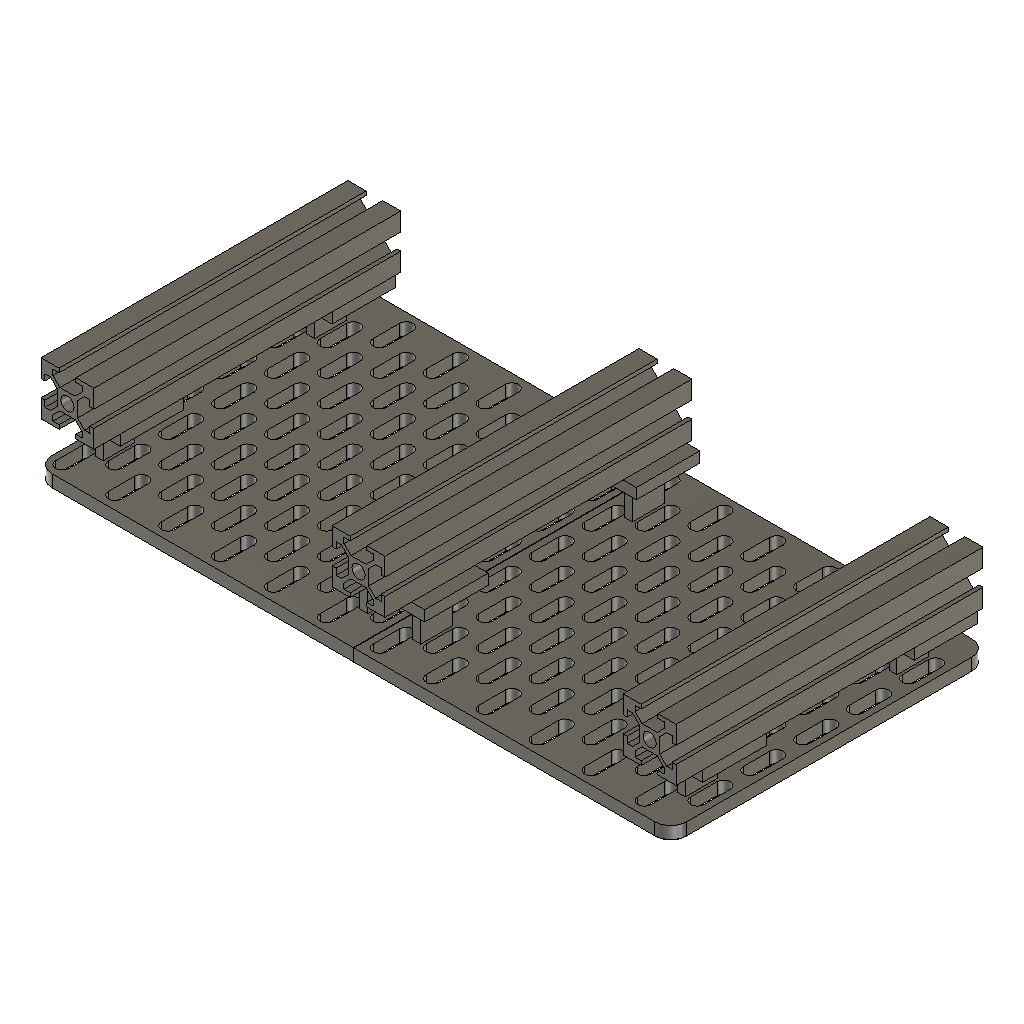
connector-clearance-study (Autodesk Fusion 360 design; units mm, degrees)
part number: 2026-10-29-08-32-22-871
part number: 2026-10-29-08-32-23-128
part number: 2026-10-29-08-32-24-920
part number: 2026-10-29-08-32-26-891
part number: 2026-10-29-08-32-27-039
part number: 2026-10-29-08-32-27-224
part number: 2026-10-29-08-32-27-440
part number: 2026-10-29-08-32-27-695
part number: 2026-10-29-08-32-27-957
part number: 2026-10-29-08-32-28-255
part number: 2026-10-29-08-32-28-585
part number: 2026-10-29-08-32-29-028
part number: 2026-10-29-08-32-29-403
part number: 2026-10-29-08-32-29-813
part number: 2026-10-29-08-32-30-268
part number: 2026-10-29-08-32-30-748
part number: 2026-10-29-08-32-31-271
part number: 2026-10-29-08-32-31-892
part number: 2026-10-29-08-32-32-475
part number: 2026-10-29-08-32-33-065
part number: 2026-10-29-08-32-33-695
part number: 2026-10-29-08-32-34-350
part number: 2026-10-29-08-32-35-130
part number: 2026-10-29-08-32-35-863
part number: 2026-10-29-08-32-36-625
part number: 2026-10-29-08-32-37-418
part number: 2026-10-29-08-32-38-300
part number: 2026-10-29-08-32-39-297
part number: 2026-10-29-08-32-40-270
part number: 2026-10-29-08-32-41-258
part number: 2026-10-29-08-32-42-385
part number: 2026-10-29-08-32-43-503
part number: 2026-10-29-08-32-44-600
part number: 2026-10-29-08-32-45-846
part number: 2026-10-29-08-32-47-039
part number: 2026-10-29-08-32-48-317
part number: 2026-10-29-08-32-49-540
part number: 2026-10-29-08-32-50-716
part number: 2026-10-29-08-32-52-129
part number: 2026-10-29-08-32-53-482
part number: 2026-10-29-08-32-54-896
part number: 2026-10-29-08-32-56-506
part number: 2026-10-29-08-33-14-715
part number: 2026-10-29-08-33-36-199
Autodesk Fusion 360 part; units mm, degrees
(part 1 of 3)
sketch "01 Panel blank sketch" plane through (0, 0, 0) normal (0, 0, 1) x (1, 0, 0) in component "Panel left - restored slot field"
  line L0 (0.1, 0.1) -> (119.9, 0.1)
  line L1 (119.9, 0.1) -> (119.9, 119.9)
  line L2 (119.9, 119.9) -> (0.1, 119.9)
  line L3 (0.1, 119.9) -> (0.1, 0.1)
  dimension "d58" = 0.1
  dimension "d59" = 0.1
  dimension "d60" = 119.8
  dimension "d61" = 119.8
  constraint horizontal L0
  constraint vertical L1
  constraint horizontal L2
  constraint vertical L3
  measures "d58" horizontal distance of origin L0.start
  measures "d59" vertical distance of origin L0.start
  measures "d60" horizontal distance of L0.start L0.end
  measures "d61" vertical distance of L0.end L1.end
extrude "01 Panel blank" add sketch "01 Panel blank sketch" along normal blind 5 makes body 1 in component "Panel left - restored slot field"
fillet "02 Exterior corner rounds" radius 6 2 edges at (0.1, 119.9, 2.5) (0.1, 0.1, 2.5) on bodies 1 in component "Panel left - restored slot field"
sketch "03 Complete A field constrained seed" plane through (0, 0, 0) normal (0, 0, 1) x (1, 0, 0) in component "Panel left - restored slot field"
  line L0 (7.5, 5) -> (7.5, 15)
  arc A0 (7.5, 15) -> (2.5, 15) centre (5, 15) ccw
  line L1 (2.5, 15) -> (2.5, 5)
  arc A1 (2.5, 5) -> (7.5, 5) centre (5, 5) ccw
  line L2 (5, 5) -> (5, 15) construction
  line L3 (5, 5) -> (15, 5) construction
  dimension "d66" = 5
  dimension "d67" = 10
  dimension "d68" = 90
  dimension "d69" = 10
  dimension "d70" = 5
  dimension "d71" = 5
  constraint tangent L0 A0
  constraint tangent A0 L1
  constraint tangent L1 A1
  constraint tangent L0 A1
  constraint parallel L0 L1
  constraint horizontal L3
  measures "d66" diameter of A0
  measures "d67" distance of A1.centre A0.centre
  measures "d68" angle of L2 L3
  measures "d69" horizontal distance of A1.centre L3.end
  measures "d70" horizontal distance of origin A1.centre
  measures "d71" vertical distance of origin A1.centre
extrude "03 Complete A field through cut" cut sketch "03 Complete A field constrained seed" along normal blind 5 bodies 1 in component "Panel left - restored slot field"
pattern_linear "03 Complete A field lattice" count 6 spacing 20 along (1, 0, 0) count 6 spacing 20 along (0, 1, 0) of "03 Complete A field through cut" in component "Panel left - restored slot field"
sketch "04 Complete B field - finished top and bottom constrained seed" plane through (0, 0, 0) normal (0, 0, 1) x (1, 0, 0) in component "Panel left - restored slot field"
  line L0 (17.5, 15) -> (17.5, 25)
  arc A0 (17.5, 25) -> (12.5, 25) centre (15, 25) ccw
  line L1 (12.5, 25) -> (12.5, 15)
  arc A1 (12.5, 15) -> (17.5, 15) centre (15, 15) ccw
  line L2 (15, 15) -> (15, 25) construction
  line L3 (15, 15) -> (25, 15) construction
  dimension "d78" = 5
  dimension "d79" = 10
  dimension "d80" = 90
  dimension "d81" = 10
  dimension "d82" = 15
  dimension "d83" = 15
  constraint tangent L0 A0
  constraint tangent A0 L1
  constraint tangent L1 A1
  constraint tangent L0 A1
  constraint parallel L0 L1
  constraint horizontal L3
  measures "d78" diameter of A0
  measures "d79" distance of A1.centre A0.centre
  measures "d80" angle of L2 L3
  measures "d81" horizontal distance of A1.centre L3.end
  measures "d82" horizontal distance of origin A1.centre
  measures "d83" vertical distance of origin A1.centre
extrude "04 Complete B field - finished top and bottom through cut" cut sketch "04 Complete B field - finished top and bottom constrained seed" along normal blind 5 bodies 1 in component "Panel left - restored slot field"
pattern_linear "04 Complete B field - finished top and bottom lattice" count 6 spacing 20 along (1, 0, 0) count 5 spacing 20 along (0, 1, 0) of "04 Complete B field - finished top and bottom through cut" in component "Panel left - restored slot field"
fillet "05 Rounded entrances and edges" radius 0.4 2 faces at (114.0711, 114.131, 0) (114.0711, 114.131, 0) on bodies 1 in component "Panel left - restored slot field"
sketch "01 Panel blank sketch (2)" plane through (0, 0, 0) normal (0, 0, 1) x (1, 0, 0) in component "Panel right - restored slot field"
  line L0 (120.1, 0.1) -> (239.9, 0.1)
  line L1 (239.9, 0.1) -> (239.9, 119.9)
  line L2 (239.9, 119.9) -> (120.1, 119.9)
  line L3 (120.1, 119.9) -> (120.1, 0.1)
  dimension "d92" = 120.1
  dimension "d93" = 0.1
  dimension "d94" = 119.8
  dimension "d95" = 119.8
  constraint horizontal L0
  constraint vertical L1
  constraint horizontal L2
  constraint vertical L3
  measures "d92" horizontal distance of origin L0.start
  measures "d93" vertical distance of origin L0.start
  measures "d94" horizontal distance of L0.start L0.end
  measures "d95" vertical distance of L0.end L1.end
extrude "01 Panel blank'" add sketch "01 Panel blank sketch (2)" along normal blind 5 separate body makes body 2 in component "Panel right - restored slot field"
fillet "02 Exterior corner rounds'" radius 6 2 edges at (239.9, 119.9, 2.5) (239.9, 0.1, 2.5) on bodies 2 in component "Panel right - restored slot field"
sketch "03 Complete A field constrained seed (2)" plane through (0, 0, 0) normal (0, 0, 1) x (1, 0, 0) in component "Panel right - restored slot field"
  line L0 (127.5, 5) -> (127.5, 15)
  arc A0 (127.5, 15) -> (122.5, 15) centre (125, 15) ccw
  line L1 (122.5, 15) -> (122.5, 5)
  arc A1 (122.5, 5) -> (127.5, 5) centre (125, 5) ccw
  line L2 (125, 5) -> (125, 15) construction
  line L3 (125, 5) -> (135, 5) construction
  dimension "d100" = 5
  dimension "d101" = 10
  dimension "d102" = 90
  dimension "d103" = 10
  dimension "d104" = 125
  dimension "d105" = 5
  constraint tangent L0 A0
  constraint tangent A0 L1
  constraint tangent L1 A1
  constraint tangent L0 A1
  constraint parallel L0 L1
  constraint horizontal L3
  measures "d100" diameter of A0
  measures "d101" distance of A1.centre A0.centre
  measures "d102" angle of L2 L3
  measures "d103" horizontal distance of A1.centre L3.end
  measures "d104" horizontal distance of origin A1.centre
  measures "d105" vertical distance of origin A1.centre
extrude "03 Complete A field through cut'" cut sketch "03 Complete A field constrained seed (2)" along normal blind 5 bodies 2 in component "Panel right - restored slot field"
pattern_linear "03 Complete A field lattice'" count 6 spacing 20 along (1, 0, 0) count 6 spacing 20 along (0, 1, 0) of "03 Complete A field through cut'" in component "Panel right - restored slot field"
sketch "04 Complete B field - finished top and bottom constrained seed (2)" plane through (0, 0, 0) normal (0, 0, 1) x (1, 0, 0) in component "Panel right - restored slot field"
  line L0 (137.5, 15) -> (137.5, 25)
  arc A0 (137.5, 25) -> (132.5, 25) centre (135, 25) ccw
  line L1 (132.5, 25) -> (132.5, 15)
  arc A1 (132.5, 15) -> (137.5, 15) centre (135, 15) ccw
  line L2 (135, 15) -> (135, 25) construction
  line L3 (135, 15) -> (145, 15) construction
  dimension "d112" = 5
  dimension "d113" = 10
  dimension "d114" = 90
  dimension "d115" = 10
  dimension "d116" = 135
  dimension "d117" = 15
  constraint tangent L0 A0
  constraint tangent A0 L1
  constraint tangent L1 A1
  constraint tangent L0 A1
  constraint parallel L0 L1
  constraint horizontal L3
  measures "d112" diameter of A0
  measures "d113" distance of A1.centre A0.centre
  measures "d114" angle of L2 L3
  measures "d115" horizontal distance of A1.centre L3.end
  measures "d116" horizontal distance of origin A1.centre
  measures "d117" vertical distance of origin A1.centre
extrude "04 Complete B field - finished top and bottom through cut'" cut sketch "04 Complete B field - finished top and bottom constrained seed (2)" along normal blind 5 bodies 2 in component "Panel right - restored slot field"
pattern_linear "04 Complete B field - finished top and bottom lattice'" count 6 spacing 20 along (1, 0, 0) count 5 spacing 20 along (0, 1, 0) of "04 Complete B field - finished top and bottom through cut'" in component "Panel right - restored slot field"
fillet "05 Rounded entrances and edges'" radius 0.4 2 faces at (135.0623, 7.5023, 0) (135.0623, 7.5023, 0) on bodies 2 in component "Panel right - restored slot field"
ref_plane "WorkPlane1" through (0, 0, 5) normal (0, 0, 1) x (1, 0, 0) in component "REFERENCE ONLY - hook insertion corridor 0"
sketch "Provisional swept hook column 0 sketch" plane through (0, 0, 5) normal (0, 0, 1) x (1, 0, 0) in component "REFERENCE ONLY - hook insertion corridor 0"
  line L0 (2, 0) -> (8, 0)
  line L1 (8, 0) -> (8, 120)
  line L2 (8, 120) -> (2, 120)
  line L3 (2, 120) -> (2, 0)
  dimension "d128" = 2
  dimension "d129" = 6
  dimension "d130" = 120
  constraint horizontal L0
  constraint vertical L1
  constraint horizontal L2
  constraint vertical L3
  constraint horizontal origin L0.start
  measures "d128" horizontal distance of origin L0.start
  measures "d129" horizontal distance of L0.start L0.end
  measures "d130" vertical distance of L0.end L1.end
extrude "Provisional swept hook column 0" add sketch "Provisional swept hook column 0 sketch" along normal blind 10 separate body makes body 3 in component "REFERENCE ONLY - hook insertion corridor 0"
ref_plane "WorkPlane1" through (0, 0, 5) normal (0, 0, 1) x (1, 0, 0) in component "REFERENCE ONLY - hook insertion corridor 1"
sketch "Provisional swept hook column 1 sketch" plane through (0, 0, 5) normal (0, 0, 1) x (1, 0, 0) in component "REFERENCE ONLY - hook insertion corridor 1"
  line L0 (12, 0) -> (18, 0)
  line L1 (18, 0) -> (18, 120)
  line L2 (18, 120) -> (12, 120)
  line L3 (12, 120) -> (12, 0)
  dimension "d135" = 12
  dimension "d136" = 6
  dimension "d137" = 120
  constraint horizontal L0
  constraint vertical L1
  constraint horizontal L2
  constraint vertical L3
  constraint horizontal origin L0.start
  measures "d135" horizontal distance of origin L0.start
  measures "d136" horizontal distance of L0.start L0.end
  measures "d137" vertical distance of L0.end L1.end
extrude "Provisional swept hook column 1" add sketch "Provisional swept hook column 1 sketch" along normal blind 10 separate body makes body 4 in component "REFERENCE ONLY - hook insertion corridor 1"
ref_plane "WorkPlane1" through (0, 0, 5) normal (0, 0, 1) x (1, 0, 0) in component "REFERENCE ONLY - hook insertion corridor 2"
sketch "Provisional swept hook column 2 sketch" plane through (0, 0, 5) normal (0, 0, 1) x (1, 0, 0) in component "REFERENCE ONLY - hook insertion corridor 2"
  line L0 (22, 0) -> (28, 0)
  line L1 (28, 0) -> (28, 120)
  line L2 (28, 120) -> (22, 120)
  line L3 (22, 120) -> (22, 0)
  dimension "d142" = 22
  dimension "d143" = 6
  dimension "d144" = 120
  constraint horizontal L0
  constraint vertical L1
  constraint horizontal L2
  constraint vertical L3
  constraint horizontal origin L0.start
  measures "d142" horizontal distance of origin L0.start
  measures "d143" horizontal distance of L0.start L0.end
  measures "d144" vertical distance of L0.end L1.end
extrude "Provisional swept hook column 2" add sketch "Provisional swept hook column 2 sketch" along normal blind 10 separate body makes body 5 in component "REFERENCE ONLY - hook insertion corridor 2"
ref_plane "WorkPlane1" through (0, 0, 5) normal (0, 0, 1) x (1, 0, 0) in component "REFERENCE ONLY - hook insertion corridor 3"
sketch "Provisional swept hook column 3 sketch" plane through (0, 0, 5) normal (0, 0, 1) x (1, 0, 0) in component "REFERENCE ONLY - hook insertion corridor 3"
  line L0 (32, 0) -> (38, 0)
  line L1 (38, 0) -> (38, 120)
  line L2 (38, 120) -> (32, 120)
  line L3 (32, 120) -> (32, 0)
  dimension "d149" = 32
  dimension "d150" = 6
  dimension "d151" = 120
  constraint horizontal L0
  constraint vertical L1
  constraint horizontal L2
  constraint vertical L3
  constraint horizontal origin L0.start
  measures "d149" horizontal distance of origin L0.start
  measures "d150" horizontal distance of L0.start L0.end
  measures "d151" vertical distance of L0.end L1.end
extrude "Provisional swept hook column 3" add sketch "Provisional swept hook column 3 sketch" along normal blind 10 separate body makes body 6 in component "REFERENCE ONLY - hook insertion corridor 3"
ref_plane "WorkPlane1" through (0, 0, 5) normal (0, 0, 1) x (1, 0, 0) in component "REFERENCE ONLY - hook insertion corridor 4"
sketch "Provisional swept hook column 4 sketch" plane through (0, 0, 5) normal (0, 0, 1) x (1, 0, 0) in component "REFERENCE ONLY - hook insertion corridor 4"
  line L0 (42, 0) -> (48, 0)
  line L1 (48, 0) -> (48, 120)
  line L2 (48, 120) -> (42, 120)
  line L3 (42, 120) -> (42, 0)
  dimension "d156" = 42
  dimension "d157" = 6
  dimension "d158" = 120
  constraint horizontal L0
  constraint vertical L1
  constraint horizontal L2
  constraint vertical L3
  constraint horizontal origin L0.start
  measures "d156" horizontal distance of origin L0.start
  measures "d157" horizontal distance of L0.start L0.end
  measures "d158" vertical distance of L0.end L1.end
extrude "Provisional swept hook column 4" add sketch "Provisional swept hook column 4 sketch" along normal blind 10 separate body makes body 7 in component "REFERENCE ONLY - hook insertion corridor 4"
ref_plane "WorkPlane1" through (0, 0, 5) normal (0, 0, 1) x (1, 0, 0) in component "REFERENCE ONLY - hook insertion corridor 5"
sketch "Provisional swept hook column 5 sketch" plane through (0, 0, 5) normal (0, 0, 1) x (1, 0, 0) in component "REFERENCE ONLY - hook insertion corridor 5"
  line L0 (52, 0) -> (58, 0)
  line L1 (58, 0) -> (58, 120)
  line L2 (58, 120) -> (52, 120)
  line L3 (52, 120) -> (52, 0)
  dimension "d163" = 52
  dimension "d164" = 6
  dimension "d165" = 120
  constraint horizontal L0
  constraint vertical L1
  constraint horizontal L2
  constraint vertical L3
  constraint horizontal origin L0.start
  measures "d163" horizontal distance of origin L0.start
  measures "d164" horizontal distance of L0.start L0.end
  measures "d165" vertical distance of L0.end L1.end
extrude "Provisional swept hook column 5" add sketch "Provisional swept hook column 5 sketch" along normal blind 10 separate body makes body 8 in component "REFERENCE ONLY - hook insertion corridor 5"
ref_plane "WorkPlane1" through (0, 0, 5) normal (0, 0, 1) x (1, 0, 0) in component "REFERENCE ONLY - hook insertion corridor 6"
sketch "Provisional swept hook column 6 sketch" plane through (0, 0, 5) normal (0, 0, 1) x (1, 0, 0) in component "REFERENCE ONLY - hook insertion corridor 6"
  line L0 (62, 0) -> (68, 0)
  line L1 (68, 0) -> (68, 120)
  line L2 (68, 120) -> (62, 120)
  line L3 (62, 120) -> (62, 0)
  dimension "d170" = 62
  dimension "d171" = 6
  dimension "d172" = 120
  constraint horizontal L0
  constraint vertical L1
  constraint horizontal L2
  constraint vertical L3
  constraint horizontal origin L0.start
  measures "d170" horizontal distance of origin L0.start
  measures "d171" horizontal distance of L0.start L0.end
  measures "d172" vertical distance of L0.end L1.end
extrude "Provisional swept hook column 6" add sketch "Provisional swept hook column 6 sketch" along normal blind 10 separate body makes body 9 in component "REFERENCE ONLY - hook insertion corridor 6"
ref_plane "WorkPlane1" through (0, 0, 5) normal (0, 0, 1) x (1, 0, 0) in component "REFERENCE ONLY - hook insertion corridor 7"
sketch "Provisional swept hook column 7 sketch" plane through (0, 0, 5) normal (0, 0, 1) x (1, 0, 0) in component "REFERENCE ONLY - hook insertion corridor 7"
  line L0 (72, 0) -> (78, 0)
  line L1 (78, 0) -> (78, 120)
  line L2 (78, 120) -> (72, 120)
  line L3 (72, 120) -> (72, 0)
  dimension "d177" = 72
  dimension "d178" = 6
  dimension "d179" = 120
  constraint horizontal L0
  constraint vertical L1
  constraint horizontal L2
  constraint vertical L3
  constraint horizontal origin L0.start
  measures "d177" horizontal distance of origin L0.start
  measures "d178" horizontal distance of L0.start L0.end
  measures "d179" vertical distance of L0.end L1.end
extrude "Provisional swept hook column 7" add sketch "Provisional swept hook column 7 sketch" along normal blind 10 separate body makes body 10 in component "REFERENCE ONLY - hook insertion corridor 7"
ref_plane "WorkPlane1" through (0, 0, 5) normal (0, 0, 1) x (1, 0, 0) in component "REFERENCE ONLY - hook insertion corridor 8"
sketch "Provisional swept hook column 8 sketch" plane through (0, 0, 5) normal (0, 0, 1) x (1, 0, 0) in component "REFERENCE ONLY - hook insertion corridor 8"
  line L0 (82, 0) -> (88, 0)
  line L1 (88, 0) -> (88, 120)
  line L2 (88, 120) -> (82, 120)
  line L3 (82, 120) -> (82, 0)
  dimension "d184" = 82
  dimension "d185" = 6
  dimension "d186" = 120
  constraint horizontal L0
  constraint vertical L1
  constraint horizontal L2
  constraint vertical L3
  constraint horizontal origin L0.start
  measures "d184" horizontal distance of origin L0.start
  measures "d185" horizontal distance of L0.start L0.end
  measures "d186" vertical distance of L0.end L1.end
extrude "Provisional swept hook column 8" add sketch "Provisional swept hook column 8 sketch" along normal blind 10 separate body makes body 11 in component "REFERENCE ONLY - hook insertion corridor 8"
ref_plane "WorkPlane1" through (0, 0, 5) normal (0, 0, 1) x (1, 0, 0) in component "REFERENCE ONLY - hook insertion corridor 9"
sketch "Provisional swept hook column 9 sketch" plane through (0, 0, 5) normal (0, 0, 1) x (1, 0, 0) in component "REFERENCE ONLY - hook insertion corridor 9"
  line L0 (92, 0) -> (98, 0)
  line L1 (98, 0) -> (98, 120)
  line L2 (98, 120) -> (92, 120)
  line L3 (92, 120) -> (92, 0)
  dimension "d191" = 92
  dimension "d192" = 6
  dimension "d193" = 120
  constraint horizontal L0
  constraint vertical L1
  constraint horizontal L2
  constraint vertical L3
  constraint horizontal origin L0.start
  measures "d191" horizontal distance of origin L0.start
  measures "d192" horizontal distance of L0.start L0.end
  measures "d193" vertical distance of L0.end L1.end
extrude "Provisional swept hook column 9" add sketch "Provisional swept hook column 9 sketch" along normal blind 10 separate body makes body 12 in component "REFERENCE ONLY - hook insertion corridor 9"
ref_plane "WorkPlane1" through (0, 0, 5) normal (0, 0, 1) x (1, 0, 0) in component "REFERENCE ONLY - hook insertion corridor 10"
sketch "Provisional swept hook column 10 sketch" plane through (0, 0, 5) normal (0, 0, 1) x (1, 0, 0) in component "REFERENCE ONLY - hook insertion corridor 10"
  line L0 (102, 0) -> (108, 0)
  line L1 (108, 0) -> (108, 120)
  line L2 (108, 120) -> (102, 120)
  line L3 (102, 120) -> (102, 0)
  dimension "d198" = 102
  dimension "d199" = 6
  dimension "d200" = 120
  constraint horizontal L0
  constraint vertical L1
  constraint horizontal L2
  constraint vertical L3
  constraint horizontal origin L0.start
  measures "d198" horizontal distance of origin L0.start
  measures "d199" horizontal distance of L0.start L0.end
  measures "d200" vertical distance of L0.end L1.end
extrude "Provisional swept hook column 10" add sketch "Provisional swept hook column 10 sketch" along normal blind 10 separate body makes body 13 in component "REFERENCE ONLY - hook insertion corridor 10"
ref_plane "WorkPlane1" through (0, 0, 5) normal (0, 0, 1) x (1, 0, 0) in component "REFERENCE ONLY - hook insertion corridor 11"
sketch "Provisional swept hook column 11 sketch" plane through (0, 0, 5) normal (0, 0, 1) x (1, 0, 0) in component "REFERENCE ONLY - hook insertion corridor 11"
  line L0 (112, 0) -> (118, 0)
  line L1 (118, 0) -> (118, 120)
  line L2 (118, 120) -> (112, 120)
  line L3 (112, 120) -> (112, 0)
  dimension "d205" = 112
  dimension "d206" = 6
  dimension "d207" = 120
  constraint horizontal L0
  constraint vertical L1
  constraint horizontal L2
  constraint vertical L3
  constraint horizontal origin L0.start
  measures "d205" horizontal distance of origin L0.start
  measures "d206" horizontal distance of L0.start L0.end
  measures "d207" vertical distance of L0.end L1.end
extrude "Provisional swept hook column 11" add sketch "Provisional swept hook column 11 sketch" along normal blind 10 separate body makes body 14 in component "REFERENCE ONLY - hook insertion corridor 11"
ref_plane "WorkPlane1" through (0, 0, 5) normal (0, 0, 1) x (1, 0, 0) in component "REFERENCE ONLY - hook insertion corridor 12"
sketch "Provisional swept hook column 12 sketch" plane through (0, 0, 5) normal (0, 0, 1) x (1, 0, 0) in component "REFERENCE ONLY - hook insertion corridor 12"
  line L0 (122, 0) -> (128, 0)
  line L1 (128, 0) -> (128, 120)
  line L2 (128, 120) -> (122, 120)
  line L3 (122, 120) -> (122, 0)
  dimension "d212" = 122
  dimension "d213" = 6
  dimension "d214" = 120
  constraint horizontal L0
  constraint vertical L1
  constraint horizontal L2
  constraint vertical L3
  constraint horizontal origin L0.start
  measures "d212" horizontal distance of origin L0.start
  measures "d213" horizontal distance of L0.start L0.end
  measures "d214" vertical distance of L0.end L1.end
extrude "Provisional swept hook column 12" add sketch "Provisional swept hook column 12 sketch" along normal blind 10 separate body makes body 15 in component "REFERENCE ONLY - hook insertion corridor 12"
ref_plane "WorkPlane1" through (0, 0, 5) normal (0, 0, 1) x (1, 0, 0) in component "REFERENCE ONLY - hook insertion corridor 13"
sketch "Provisional swept hook column 13 sketch" plane through (0, 0, 5) normal (0, 0, 1) x (1, 0, 0) in component "REFERENCE ONLY - hook insertion corridor 13"
  line L0 (132, 0) -> (138, 0)
  line L1 (138, 0) -> (138, 120)
  line L2 (138, 120) -> (132, 120)
  line L3 (132, 120) -> (132, 0)
  dimension "d219" = 132
  dimension "d220" = 6
  dimension "d221" = 120
  constraint horizontal L0
  constraint vertical L1
  constraint horizontal L2
  constraint vertical L3
  constraint horizontal origin L0.start
  measures "d219" horizontal distance of origin L0.start
  measures "d220" horizontal distance of L0.start L0.end
  measures "d221" vertical distance of L0.end L1.end
extrude "Provisional swept hook column 13" add sketch "Provisional swept hook column 13 sketch" along normal blind 10 separate body makes body 16 in component "REFERENCE ONLY - hook insertion corridor 13"
ref_plane "WorkPlane1" through (0, 0, 5) normal (0, 0, 1) x (1, 0, 0) in component "REFERENCE ONLY - hook insertion corridor 14"
sketch "Provisional swept hook column 14 sketch" plane through (0, 0, 5) normal (0, 0, 1) x (1, 0, 0) in component "REFERENCE ONLY - hook insertion corridor 14"
  line L0 (142, 0) -> (148, 0)
  line L1 (148, 0) -> (148, 120)
  line L2 (148, 120) -> (142, 120)
  line L3 (142, 120) -> (142, 0)
  dimension "d226" = 142
  dimension "d227" = 6
  dimension "d228" = 120
  constraint horizontal L0
  constraint vertical L1
  constraint horizontal L2
  constraint vertical L3
  constraint horizontal origin L0.start
  measures "d226" horizontal distance of origin L0.start
  measures "d227" horizontal distance of L0.start L0.end
  measures "d228" vertical distance of L0.end L1.end
extrude "Provisional swept hook column 14" add sketch "Provisional swept hook column 14 sketch" along normal blind 10 separate body makes body 17 in component "REFERENCE ONLY - hook insertion corridor 14"
ref_plane "WorkPlane1" through (0, 0, 5) normal (0, 0, 1) x (1, 0, 0) in component "REFERENCE ONLY - hook insertion corridor 15"
sketch "Provisional swept hook column 15 sketch" plane through (0, 0, 5) normal (0, 0, 1) x (1, 0, 0) in component "REFERENCE ONLY - hook insertion corridor 15"
  line L0 (152, 0) -> (158, 0)
  line L1 (158, 0) -> (158, 120)
  line L2 (158, 120) -> (152, 120)
  line L3 (152, 120) -> (152, 0)
  dimension "d233" = 152
  dimension "d234" = 6
  dimension "d235" = 120
  constraint horizontal L0
  constraint vertical L1
  constraint horizontal L2
  constraint vertical L3
  constraint horizontal origin L0.start
  measures "d233" horizontal distance of origin L0.start
  measures "d234" horizontal distance of L0.start L0.end
  measures "d235" vertical distance of L0.end L1.end
extrude "Provisional swept hook column 15" add sketch "Provisional swept hook column 15 sketch" along normal blind 10 separate body makes body 18 in component "REFERENCE ONLY - hook insertion corridor 15"
ref_plane "WorkPlane1" through (0, 0, 5) normal (0, 0, 1) x (1, 0, 0) in component "REFERENCE ONLY - hook insertion corridor 16"
sketch "Provisional swept hook column 16 sketch" plane through (0, 0, 5) normal (0, 0, 1) x (1, 0, 0) in component "REFERENCE ONLY - hook insertion corridor 16"
  line L0 (162, 0) -> (168, 0)
  line L1 (168, 0) -> (168, 120)
  line L2 (168, 120) -> (162, 120)
  line L3 (162, 120) -> (162, 0)
  dimension "d240" = 162
  dimension "d241" = 6
  dimension "d242" = 120
  constraint horizontal L0
  constraint vertical L1
  constraint horizontal L2
  constraint vertical L3
  constraint horizontal origin L0.start
  measures "d240" horizontal distance of origin L0.start
  measures "d241" horizontal distance of L0.start L0.end
  measures "d242" vertical distance of L0.end L1.end
extrude "Provisional swept hook column 16" add sketch "Provisional swept hook column 16 sketch" along normal blind 10 separate body makes body 19 in component "REFERENCE ONLY - hook insertion corridor 16"
ref_plane "WorkPlane1" through (0, 0, 5) normal (0, 0, 1) x (1, 0, 0) in component "REFERENCE ONLY - hook insertion corridor 17"
sketch "Provisional swept hook column 17 sketch" plane through (0, 0, 5) normal (0, 0, 1) x (1, 0, 0) in component "REFERENCE ONLY - hook insertion corridor 17"
  line L0 (172, 0) -> (178, 0)
  line L1 (178, 0) -> (178, 120)
  line L2 (178, 120) -> (172, 120)
  line L3 (172, 120) -> (172, 0)
  dimension "d247" = 172
  dimension "d248" = 6
  dimension "d249" = 120
  constraint horizontal L0
  constraint vertical L1
  constraint horizontal L2
  constraint vertical L3
  constraint horizontal origin L0.start
  measures "d247" horizontal distance of origin L0.start
  measures "d248" horizontal distance of L0.start L0.end
  measures "d249" vertical distance of L0.end L1.end
extrude "Provisional swept hook column 17" add sketch "Provisional swept hook column 17 sketch" along normal blind 10 separate body makes body 20 in component "REFERENCE ONLY - hook insertion corridor 17"
ref_plane "WorkPlane1" through (0, 0, 5) normal (0, 0, 1) x (1, 0, 0) in component "REFERENCE ONLY - hook insertion corridor 18"
sketch "Provisional swept hook column 18 sketch" plane through (0, 0, 5) normal (0, 0, 1) x (1, 0, 0) in component "REFERENCE ONLY - hook insertion corridor 18"
  line L0 (182, 0) -> (188, 0)
  line L1 (188, 0) -> (188, 120)
  line L2 (188, 120) -> (182, 120)
  line L3 (182, 120) -> (182, 0)
  dimension "d254" = 182
  dimension "d255" = 6
  dimension "d256" = 120
  constraint horizontal L0
  constraint vertical L1
  constraint horizontal L2
  constraint vertical L3
  constraint horizontal origin L0.start
  measures "d254" horizontal distance of origin L0.start
  measures "d255" horizontal distance of L0.start L0.end
  measures "d256" vertical distance of L0.end L1.end
extrude "Provisional swept hook column 18" add sketch "Provisional swept hook column 18 sketch" along normal blind 10 separate body makes body 21 in component "REFERENCE ONLY - hook insertion corridor 18"
ref_plane "WorkPlane1" through (0, 0, 5) normal (0, 0, 1) x (1, 0, 0) in component "REFERENCE ONLY - hook insertion corridor 19"
sketch "Provisional swept hook column 19 sketch" plane through (0, 0, 5) normal (0, 0, 1) x (1, 0, 0) in component "REFERENCE ONLY - hook insertion corridor 19"
  line L0 (192, 0) -> (198, 0)
  line L1 (198, 0) -> (198, 120)
  line L2 (198, 120) -> (192, 120)
  line L3 (192, 120) -> (192, 0)
  dimension "d261" = 192
  dimension "d262" = 6
  dimension "d263" = 120
  constraint horizontal L0
  constraint vertical L1
  constraint horizontal L2
  constraint vertical L3
  constraint horizontal origin L0.start
  measures "d261" horizontal distance of origin L0.start
  measures "d262" horizontal distance of L0.start L0.end
  measures "d263" vertical distance of L0.end L1.end
extrude "Provisional swept hook column 19" add sketch "Provisional swept hook column 19 sketch" along normal blind 10 separate body makes body 22 in component "REFERENCE ONLY - hook insertion corridor 19"
ref_plane "WorkPlane1" through (0, 0, 5) normal (0, 0, 1) x (1, 0, 0) in component "REFERENCE ONLY - hook insertion corridor 20"
sketch "Provisional swept hook column 20 sketch" plane through (0, 0, 5) normal (0, 0, 1) x (1, 0, 0) in component "REFERENCE ONLY - hook insertion corridor 20"
  line L0 (202, 0) -> (208, 0)
  line L1 (208, 0) -> (208, 120)
  line L2 (208, 120) -> (202, 120)
  line L3 (202, 120) -> (202, 0)
  dimension "d268" = 202
  dimension "d269" = 6
  dimension "d270" = 120
  constraint horizontal L0
  constraint vertical L1
  constraint horizontal L2
  constraint vertical L3
  constraint horizontal origin L0.start
  measures "d268" horizontal distance of origin L0.start
  measures "d269" horizontal distance of L0.start L0.end
  measures "d270" vertical distance of L0.end L1.end
extrude "Provisional swept hook column 20" add sketch "Provisional swept hook column 20 sketch" along normal blind 10 separate body makes body 23 in component "REFERENCE ONLY - hook insertion corridor 20"
ref_plane "WorkPlane1" through (0, 0, 5) normal (0, 0, 1) x (1, 0, 0) in component "REFERENCE ONLY - hook insertion corridor 21"
sketch "Provisional swept hook column 21 sketch" plane through (0, 0, 5) normal (0, 0, 1) x (1, 0, 0) in component "REFERENCE ONLY - hook insertion corridor 21"
  line L0 (212, 0) -> (218, 0)
  line L1 (218, 0) -> (218, 120)
  line L2 (218, 120) -> (212, 120)
  line L3 (212, 120) -> (212, 0)
  dimension "d275" = 212
  dimension "d276" = 6
  dimension "d277" = 120
  constraint horizontal L0
  constraint vertical L1
  constraint horizontal L2
  constraint vertical L3
  constraint horizontal origin L0.start
  measures "d275" horizontal distance of origin L0.start
  measures "d276" horizontal distance of L0.start L0.end
  measures "d277" vertical distance of L0.end L1.end
extrude "Provisional swept hook column 21" add sketch "Provisional swept hook column 21 sketch" along normal blind 10 separate body makes body 24 in component "REFERENCE ONLY - hook insertion corridor 21"
ref_plane "WorkPlane1" through (0, 0, 5) normal (0, 0, 1) x (1, 0, 0) in component "REFERENCE ONLY - hook insertion corridor 22"
sketch "Provisional swept hook column 22 sketch" plane through (0, 0, 5) normal (0, 0, 1) x (1, 0, 0) in component "REFERENCE ONLY - hook insertion corridor 22"
  line L0 (222, 0) -> (228, 0)
  line L1 (228, 0) -> (228, 120)
  line L2 (228, 120) -> (222, 120)
  line L3 (222, 120) -> (222, 0)
  dimension "d282" = 222
  dimension "d283" = 6
  dimension "d284" = 120
  constraint horizontal L0
  constraint vertical L1
  constraint horizontal L2
  constraint vertical L3
  constraint horizontal origin L0.start
  measures "d282" horizontal distance of origin L0.start
  measures "d283" horizontal distance of L0.start L0.end
  measures "d284" vertical distance of L0.end L1.end
extrude "Provisional swept hook column 22" add sketch "Provisional swept hook column 22 sketch" along normal blind 10 separate body makes body 25 in component "REFERENCE ONLY - hook insertion corridor 22"
ref_plane "WorkPlane1" through (0, 0, 5) normal (0, 0, 1) x (1, 0, 0) in component "REFERENCE ONLY - hook insertion corridor 23"
sketch "Provisional swept hook column 23 sketch" plane through (0, 0, 5) normal (0, 0, 1) x (1, 0, 0) in component "REFERENCE ONLY - hook insertion corridor 23"
  line L0 (232, 0) -> (238, 0)
  line L1 (238, 0) -> (238, 120)
  line L2 (238, 120) -> (232, 120)
  line L3 (232, 120) -> (232, 0)
  dimension "d289" = 232
  dimension "d290" = 6
  dimension "d291" = 120
  constraint horizontal L0
  constraint vertical L1
  constraint horizontal L2
  constraint vertical L3
  constraint horizontal origin L0.start
  measures "d289" horizontal distance of origin L0.start
  measures "d290" horizontal distance of L0.start L0.end
  measures "d291" vertical distance of L0.end L1.end
extrude "Provisional swept hook column 23" add sketch "Provisional swept hook column 23 sketch" along normal blind 10 separate body makes body 26 in component "REFERENCE ONLY - hook insertion corridor 23"
ref_plane "WorkPlane1" through (0, 0, 5) normal (0, 0, 1) x (1, 0, 0) in component "CONCEPT support blade - retention NOT DESIGNED"
sketch "Solid-web support envelope sketch" plane through (0, 0, 5) normal (0, 0, 1) x (1, 0, 0) in component "CONCEPT support blade - retention NOT DESIGNED"
  line L0 (8.5, 14) -> (11.5, 14)
  line L1 (11.5, 14) -> (11.5, 26)
  line L2 (11.5, 26) -> (8.5, 26)
  line L3 (8.5, 26) -> (8.5, 14)
  dimension "d296" = 8.5
  dimension "d297" = 14
  dimension "d298" = 3
  dimension "d299" = 12
  constraint horizontal L0
  constraint vertical L1
  constraint horizontal L2
  constraint vertical L3
  measures "d296" horizontal distance of origin L0.start
  measures "d297" vertical distance of origin L0.start
  measures "d298" horizontal distance of L0.start L0.end
  measures "d299" vertical distance of L0.end L1.end
extrude "Solid-web support envelope" add sketch "Solid-web support envelope sketch" along normal blind 10 separate body makes body 27 in component "CONCEPT support blade - retention NOT DESIGNED"
ref_plane "WorkPlane1" through (0, 0, 5) normal (0, 0, 1) x (1, 0, 0) in component "CONCEPT support blade - retention NOT DESIGNED (1)"
sketch "Solid-web support envelope sketch (2)" plane through (0, 0, 5) normal (0, 0, 1) x (1, 0, 0) in component "CONCEPT support blade - retention NOT DESIGNED (1)"
  line L0 (8.5, 94) -> (11.5, 94)
  line L1 (11.5, 94) -> (11.5, 106)
  line L2 (11.5, 106) -> (8.5, 106)
  line L3 (8.5, 106) -> (8.5, 94)
  dimension "d304" = 8.5
  dimension "d305" = 94
  dimension "d306" = 3
  dimension "d307" = 12
  constraint horizontal L0
  constraint vertical L1
  constraint horizontal L2
  constraint vertical L3
  measures "d304" horizontal distance of origin L0.start
  measures "d305" vertical distance of origin L0.start
  measures "d306" horizontal distance of L0.start L0.end
  measures "d307" vertical distance of L0.end L1.end
extrude "Solid-web support envelope'" add sketch "Solid-web support envelope sketch (2)" along normal blind 10 separate body makes body 28 in component "CONCEPT support blade - retention NOT DESIGNED (1)"
ref_plane "WorkPlane1" through (0, 0, 5) normal (0, 0, 1) x (1, 0, 0) in component "CONCEPT support blade - retention NOT DESIGNED (2)"
sketch "Solid-web support envelope sketch (3)" plane through (0, 0, 5) normal (0, 0, 1) x (1, 0, 0) in component "CONCEPT support blade - retention NOT DESIGNED (2)"
  line L0 (108.5, 14) -> (111.5, 14)
  line L1 (111.5, 14) -> (111.5, 26)
  line L2 (111.5, 26) -> (108.5, 26)
  line L3 (108.5, 26) -> (108.5, 14)
  dimension "d312" = 108.5
  dimension "d313" = 14
  dimension "d314" = 3
  dimension "d315" = 12
  constraint horizontal L0
  constraint vertical L1
  constraint horizontal L2
  constraint vertical L3
  measures "d312" horizontal distance of origin L0.start
  measures "d313" vertical distance of origin L0.start
  measures "d314" horizontal distance of L0.start L0.end
  measures "d315" vertical distance of L0.end L1.end
extrude "Solid-web support envelope''" add sketch "Solid-web support envelope sketch (3)" along normal blind 10 separate body makes body 29 in component "CONCEPT support blade - retention NOT DESIGNED (2)"
ref_plane "WorkPlane1" through (0, 0, 5) normal (0, 0, 1) x (1, 0, 0) in component "CONCEPT support blade - retention NOT DESIGNED (3)"
sketch "Solid-web support envelope sketch (4)" plane through (0, 0, 5) normal (0, 0, 1) x (1, 0, 0) in component "CONCEPT support blade - retention NOT DESIGNED (3)"
  line L0 (108.5, 94) -> (111.5, 94)
  line L1 (111.5, 94) -> (111.5, 106)
  line L2 (111.5, 106) -> (108.5, 106)
  line L3 (108.5, 106) -> (108.5, 94)
  dimension "d320" = 108.5
  dimension "d321" = 94
  dimension "d322" = 3
  dimension "d323" = 12
  constraint horizontal L0
  constraint vertical L1
  constraint horizontal L2
  constraint vertical L3
  measures "d320" horizontal distance of origin L0.start
  measures "d321" vertical distance of origin L0.start
  measures "d322" horizontal distance of L0.start L0.end
  measures "d323" vertical distance of L0.end L1.end
extrude "Solid-web support envelope'''" add sketch "Solid-web support envelope sketch (4)" along normal blind 10 separate body makes body 30 in component "CONCEPT support blade - retention NOT DESIGNED (3)"
ref_plane "WorkPlane1" through (0, 0, 5) normal (0, 0, 1) x (1, 0, 0) in component "CONCEPT support blade - retention NOT DESIGNED (4)"
sketch "Solid-web support envelope sketch (5)" plane through (0, 0, 5) normal (0, 0, 1) x (1, 0, 0) in component "CONCEPT support blade - retention NOT DESIGNED (4)"
  line L0 (128.5, 14) -> (131.5, 14)
  line L1 (131.5, 14) -> (131.5, 26)
  line L2 (131.5, 26) -> (128.5, 26)
  line L3 (128.5, 26) -> (128.5, 14)
  dimension "d328" = 128.5
  dimension "d329" = 14
  dimension "d330" = 3
  dimension "d331" = 12
  constraint horizontal L0
  constraint vertical L1
  constraint horizontal L2
  constraint vertical L3
  measures "d328" horizontal distance of origin L0.start
  measures "d329" vertical distance of origin L0.start
  measures "d330" horizontal distance of L0.start L0.end
  measures "d331" vertical distance of L0.end L1.end
extrude "Solid-web support envelope''''" add sketch "Solid-web support envelope sketch (5)" along normal blind 10 separate body makes body 31 in component "CONCEPT support blade - retention NOT DESIGNED (4)"
ref_plane "WorkPlane1" through (0, 0, 5) normal (0, 0, 1) x (1, 0, 0) in component "CONCEPT support blade - retention NOT DESIGNED (5)"
sketch "Solid-web support envelope sketch (6)" plane through (0, 0, 5) normal (0, 0, 1) x (1, 0, 0) in component "CONCEPT support blade - retention NOT DESIGNED (5)"
  line L0 (128.5, 94) -> (131.5, 94)
  line L1 (131.5, 94) -> (131.5, 106)
  line L2 (131.5, 106) -> (128.5, 106)
  line L3 (128.5, 106) -> (128.5, 94)
  dimension "d336" = 128.5
  dimension "d337" = 94
  dimension "d338" = 3
  dimension "d339" = 12
  constraint horizontal L0
  constraint vertical L1
  constraint horizontal L2
  constraint vertical L3
  measures "d336" horizontal distance of origin L0.start
  measures "d337" vertical distance of origin L0.start
  measures "d338" horizontal distance of L0.start L0.end
  measures "d339" vertical distance of L0.end L1.end
extrude "Solid-web support envelope'''''" add sketch "Solid-web support envelope sketch (6)" along normal blind 10 separate body makes body 32 in component "CONCEPT support blade - retention NOT DESIGNED (5)"
ref_plane "WorkPlane1" through (0, 0, 5) normal (0, 0, 1) x (1, 0, 0) in component "CONCEPT support blade - retention NOT DESIGNED (6)"
sketch "Solid-web support envelope sketch (7)" plane through (0, 0, 5) normal (0, 0, 1) x (1, 0, 0) in component "CONCEPT support blade - retention NOT DESIGNED (6)"
  line L0 (228.5, 14) -> (231.5, 14)
  line L1 (231.5, 14) -> (231.5, 26)
  line L2 (231.5, 26) -> (228.5, 26)
  line L3 (228.5, 26) -> (228.5, 14)
  dimension "d344" = 228.5
  dimension "d345" = 14
  dimension "d346" = 3
  dimension "d347" = 12
  constraint horizontal L0
  constraint vertical L1
  constraint horizontal L2
  constraint vertical L3
  measures "d344" horizontal distance of origin L0.start
  measures "d345" vertical distance of origin L0.start
  measures "d346" horizontal distance of L0.start L0.end
  measures "d347" vertical distance of L0.end L1.end
extrude "Solid-web support envelope''''''" add sketch "Solid-web support envelope sketch (7)" along normal blind 10 separate body makes body 33 in component "CONCEPT support blade - retention NOT DESIGNED (6)"
ref_plane "WorkPlane1" through (0, 0, 5) normal (0, 0, 1) x (1, 0, 0) in component "CONCEPT support blade - retention NOT DESIGNED (7)"
sketch "Solid-web support envelope sketch (8)" plane through (0, 0, 5) normal (0, 0, 1) x (1, 0, 0) in component "CONCEPT support blade - retention NOT DESIGNED (7)"
  line L0 (228.5, 94) -> (231.5, 94)
  line L1 (231.5, 94) -> (231.5, 106)
  line L2 (231.5, 106) -> (228.5, 106)
  line L3 (228.5, 106) -> (228.5, 94)
  dimension "d352" = 228.5
  dimension "d353" = 94
  dimension "d354" = 3
  dimension "d355" = 12
  constraint horizontal L0
  constraint vertical L1
  constraint horizontal L2
  constraint vertical L3
  measures "d352" horizontal distance of origin L0.start
  measures "d353" vertical distance of origin L0.start
  measures "d354" horizontal distance of L0.start L0.end
  measures "d355" vertical distance of L0.end L1.end
extrude "Solid-web support envelope'''''''" add sketch "Solid-web support envelope sketch (8)" along normal blind 10 separate body makes body 34 in component "CONCEPT support blade - retention NOT DESIGNED (7)"
ref_plane "WorkPlane1" through (0, 0, 15) normal (0, 0, 1) x (1, 0, 0) in component "CONCEPT carrier envelope - hardware NOT DESIGNED"
sketch "Rear carrier space reservation sketch" plane through (0, 0, 15) normal (0, 0, 1) x (1, 0, 0) in component "CONCEPT carrier envelope - hardware NOT DESIGNED"
  line L0 (0, 12) -> (20, 12)
  line L1 (20, 12) -> (20, 36)
  line L2 (20, 36) -> (0, 36)
  line L3 (0, 36) -> (0, 12)
  dimension "d360" = 12
  dimension "d361" = 20
  dimension "d362" = 24
  constraint horizontal L0
  constraint vertical L1
  constraint horizontal L2
  constraint vertical L3
  constraint vertical origin L0.start
  measures "d360" vertical distance of origin L0.start
  measures "d361" horizontal distance of L0.start L0.end
  measures "d362" vertical distance of L0.end L1.end
extrude "Rear carrier space reservation" add sketch "Rear carrier space reservation sketch" along normal blind 4 separate body makes body 35 in component "CONCEPT carrier envelope - hardware NOT DESIGNED"
ref_plane "WorkPlane1" through (0, 0, 15) normal (0, 0, 1) x (1, 0, 0) in component "CONCEPT carrier envelope - hardware NOT DESIGNED (1)"
sketch "Rear carrier space reservation sketch (2)" plane through (0, 0, 15) normal (0, 0, 1) x (1, 0, 0) in component "CONCEPT carrier envelope - hardware NOT DESIGNED (1)"
  line L0 (0, 92) -> (20, 92)
  line L1 (20, 92) -> (20, 116)
  line L2 (20, 116) -> (0, 116)
  line L3 (0, 116) -> (0, 92)
  dimension "d367" = 92
  dimension "d368" = 20
  dimension "d369" = 24
  constraint horizontal L0
  constraint vertical L1
  constraint horizontal L2
  constraint vertical L3
  constraint vertical origin L0.start
  measures "d367" vertical distance of origin L0.start
  measures "d368" horizontal distance of L0.start L0.end
  measures "d369" vertical distance of L0.end L1.end
extrude "Rear carrier space reservation'" add sketch "Rear carrier space reservation sketch (2)" along normal blind 4 separate body makes body 36 in component "CONCEPT carrier envelope - hardware NOT DESIGNED (1)"
ref_plane "WorkPlane1" through (0, 0, 15) normal (0, 0, 1) x (1, 0, 0) in component "CONCEPT carrier envelope - hardware NOT DESIGNED (2)"
sketch "Rear carrier space reservation sketch (3)" plane through (0, 0, 15) normal (0, 0, 1) x (1, 0, 0) in component "CONCEPT carrier envelope - hardware NOT DESIGNED (2)"
  line L0 (105, 12) -> (135, 12)
  line L1 (135, 12) -> (135, 36)
  line L2 (135, 36) -> (105, 36)
  line L3 (105, 36) -> (105, 12)
  dimension "d374" = 105
  dimension "d375" = 12
  dimension "d376" = 30
  dimension "d377" = 24
  constraint horizontal L0
  constraint vertical L1
  constraint horizontal L2
  constraint vertical L3
  measures "d374" horizontal distance of origin L0.start
  measures "d375" vertical distance of origin L0.start
  measures "d376" horizontal distance of L0.start L0.end
  measures "d377" vertical distance of L0.end L1.end
extrude "Rear carrier space reservation''" add sketch "Rear carrier space reservation sketch (3)" along normal blind 4 separate body makes body 37 in component "CONCEPT carrier envelope - hardware NOT DESIGNED (2)"
ref_plane "WorkPlane1" through (0, 0, 15) normal (0, 0, 1) x (1, 0, 0) in component "CONCEPT carrier envelope - hardware NOT DESIGNED (3)"
sketch "Rear carrier space reservation sketch (4)" plane through (0, 0, 15) normal (0, 0, 1) x (1, 0, 0) in component "CONCEPT carrier envelope - hardware NOT DESIGNED (3)"
  line L0 (105, 92) -> (135, 92)
  line L1 (135, 92) -> (135, 116)
  line L2 (135, 116) -> (105, 116)
  line L3 (105, 116) -> (105, 92)
  dimension "d382" = 105
  dimension "d383" = 92
  dimension "d384" = 30
  dimension "d385" = 24
  constraint horizontal L0
  constraint vertical L1
  constraint horizontal L2
  constraint vertical L3
  measures "d382" horizontal distance of origin L0.start
  measures "d383" vertical distance of origin L0.start
  measures "d384" horizontal distance of L0.start L0.end
  measures "d385" vertical distance of L0.end L1.end
extrude "Rear carrier space reservation'''" add sketch "Rear carrier space reservation sketch (4)" along normal blind 4 separate body makes body 38 in component "CONCEPT carrier envelope - hardware NOT DESIGNED (3)"
ref_plane "WorkPlane1" through (0, 0, 15) normal (0, 0, 1) x (1, 0, 0) in component "CONCEPT carrier envelope - hardware NOT DESIGNED (4)"
sketch "Rear carrier space reservation sketch (5)" plane through (0, 0, 15) normal (0, 0, 1) x (1, 0, 0) in component "CONCEPT carrier envelope - hardware NOT DESIGNED (4)"
  line L0 (220, 12) -> (240, 12)
  line L1 (240, 12) -> (240, 36)
  line L2 (240, 36) -> (220, 36)
  line L3 (220, 36) -> (220, 12)
  dimension "d390" = 220
  dimension "d391" = 12
  dimension "d392" = 20
  dimension "d393" = 24
  constraint horizontal L0
  constraint vertical L1
  constraint horizontal L2
  constraint vertical L3
  measures "d390" horizontal distance of origin L0.start
  measures "d391" vertical distance of origin L0.start
  measures "d392" horizontal distance of L0.start L0.end
  measures "d393" vertical distance of L0.end L1.end
extrude "Rear carrier space reservation''''" add sketch "Rear carrier space reservation sketch (5)" along normal blind 4 separate body makes body 39 in component "CONCEPT carrier envelope - hardware NOT DESIGNED (4)"
ref_plane "WorkPlane1" through (0, 0, 15) normal (0, 0, 1) x (1, 0, 0) in component "CONCEPT carrier envelope - hardware NOT DESIGNED (5)"
sketch "Rear carrier space reservation sketch (6)" plane through (0, 0, 15) normal (0, 0, 1) x (1, 0, 0) in component "CONCEPT carrier envelope - hardware NOT DESIGNED (5)"
  line L0 (220, 92) -> (240, 92)
  line L1 (240, 92) -> (240, 116)
  line L2 (240, 116) -> (220, 116)
  line L3 (220, 116) -> (220, 92)
  dimension "d398" = 220
  dimension "d399" = 92
  dimension "d400" = 20
  dimension "d401" = 24
  constraint horizontal L0
  constraint vertical L1
  constraint horizontal L2
  constraint vertical L3
  measures "d398" horizontal distance of origin L0.start
  measures "d399" vertical distance of origin L0.start
  measures "d400" horizontal distance of L0.start L0.end
  measures "d401" vertical distance of L0.end L1.end
extrude "Rear carrier space reservation'''''" add sketch "Rear carrier space reservation sketch (6)" along normal blind 4 separate body makes body 40 in component "CONCEPT carrier envelope - hardware NOT DESIGNED (5)"
ref_plane "WorkPlane1" through (0, 2, 0) normal (0, 1, 0) x (0, 0, 1) in component "REFERENCE 2020 rail 0 - measured sloped-slot approximation"